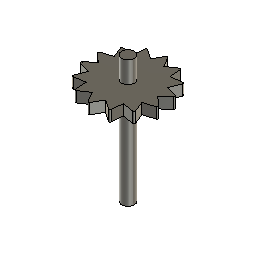
base assembly (Autodesk Fusion 360 archive; units mm, degrees)
design "in gear 2"
part number: 2026-03-27-23-33-12-431
Autodesk Fusion 360 part; units mm, degrees
(part 1 of 2)
sketch "Sketch1" plane through (0, 0, 0) normal (0, 0, 1) x (1, 0, 0)
  circle A0 centre (0, 0) radius 3
  dimension "d1" = 6
  constraint coincident A0.centre origin
  measures "d1" diameter of A0
extrude "Extrude1" add sketch "Sketch1" along normal blind 49.5
sketch "Sketch2" plane through (0, 0, 49.5) normal (0, 0, 1) x (-1, 0, 0)
  circle A0 centre (0, 0) radius 3
  circle A1 centre (0, 0) radius 13.5
  dimension "d4" = 27
  constraint concentric A0 A1
  measures "d4" diameter of A1
extrude "Extrude2" add sketch "Sketch2" against normal blind 5
sketch "Sketch3" plane through (0, 0, 49.5) normal (0, 0, 1) x (-1, 0, 0)
  circle A0 centre (0, 0) radius 13.5
  line L0 (-3.4641, -13.048) -> (0, -19.048)
  line L1 (0, -19.048) -> (3.4641, -13.048)
  line L2 (3.4641, -13.048) -> (-3.4641, -13.048)
  point P0 (0, -15.048)
  dimension "d7" = 2
  constraint horizontal L2
  constraint coincident A0 L1.end
  constraint coincident A0 L0.start
  measures "d7" distance of P0 L2
extrude "Extrude3" add sketch "Sketch3" against normal up to surface (5 mm away) contours A0 L0 L1
fillet "Fillet1" radius 0.5 1 edges at (0, 19.048, 47)
sketch "Sketch5" plane through (0, 0, 49.5) normal (0, 0, 1) x (-1, 0, 0)
  line L0 (-3.4641, -13.048) -> (-0.433, -18.298)
  arc A0 (-0.433, -18.298) -> (0.433, -18.298) centre (0, -18.048) ccw
  line L1 (0.433, -18.298) -> (3.4641, -13.048)
  circle A1 centre (0, 0) radius 3
  arc A2 (3.4641, -13.048) -> (-3.4641, -13.048) centre (0, 0) ccw
  constraint coincident A1.centre A2.centre
extrude "Extrude5" add sketch "Sketch5" along normal blind 10 contours A1
pattern_circular "C-Pattern2" count 14 over 360 about axis through (0, 0, 1.75) along (0, 0, 1) of "Extrude3", "Fillet1"

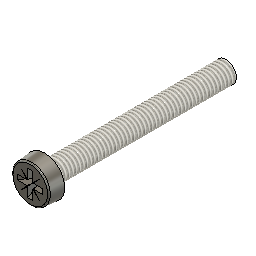
design "Cheese Head Screw NF EN ISO 7048 - M3 x 25 - Z Steel 4.6 Plain"
description: Cheese Head Screw NF EN ISO 7048 - M3 x 25 - Z
part number: NF EN ISO 7048 - Z - M3 x 25 Steel 4.6 Plain
Autodesk Fusion 360 part; units mm, degrees
sketch "Sketch1" plane through (0, 0, 0) normal (0, 1, 0) x (1, 0, 0)
  line L0 (0, -2) -> (0, 25)
  line L1 (-2.75, 0) -> (-2.575, -2)
  line L2 (-2.75, 0) -> (-1.325, 0)
  line L3 (0, 25) -> (-1.5, 25)
  line L4 (-1.5, 25) -> (-1.5, 1)
  line L5 (-1.5, 1) -> (-1.325, 0.3469)
  line L6 (-1.325, 0.3469) -> (-1.325, 0)
  line L7 (0, -2) -> (-2.575, -2)
  dimension "d13" = 5
  dimension "d14" = 5.5
  dimension "d18" = 3
  dimension "d56" = 25
  dimension "d65" = 15
  dimension "d71" = 2.65
  dimension "d77" = 1
  dimension "d97" = 2
  constraint vertical L0
  constraint coincident origin L0
  constraint coincident origin L2
  constraint coincident L2.end L6.end
  constraint perpendicular L0 L7
  measures "d13" angle of L0 L1
  measures "d56" distance of L2 L3
  measures "d65" angle of L5 L6
  measures "d77" distance of L2 L4.end
  measures "d97" distance of L2 L7
revolve "Revolve1" add sketch "Sketch1" angle 360 about axis through (0, 0, 2) along (0, 0, -1) makes body 1
fillet "Fillet3" radius 0.2 1 edges at (-2.4008, 0.9312, 2) on bodies 1
fillet "Fillet2" radius 0.1 1 edges at (-1.2353, 0.4791, 0) on bodies 1
sketch "Sketch2" plane through (0, 0, 2) normal (0, 0, 1) x (1, 0, 0)
  line L0 (-0.42, -0.42) -> (0.42, -0.42)
  line L1 (0.42, -0.42) -> (0.42, 0.42)
  line L2 (0.42, 0.42) -> (-0.42, 0.42)
  line L3 (-0.42, 0.42) -> (-0.42, -0.42)
  dimension "d98" = 0.84
  constraint vertical L1
  measures "d98" distance of L0 L2
extrude "Extrude2" add sketch "Sketch2" against normal blind 0.976 draft -10 separate body makes body 2
sketch "Sketch3" plane through (0, 0, 2) normal (0, 0, 1) x (1, 0, 0)
  circle A0 centre (0, 0) radius 2.3918
  line L0 (-0.35, 0.35) -> (-1.75, 0.35)
  line L1 (-1.75, 0.35) -> (-1.75, -0.35)
  line L2 (-1.75, -0.35) -> (-0.35, -0.35)
  line L3 (-0.35, -0.35) -> (-0.35, -1.75)
  line L4 (-0.35, -1.75) -> (0.35, -1.75)
  line L5 (0.35, -1.75) -> (0.35, -0.35)
  line L6 (0.35, -0.35) -> (1.75, -0.35)
  line L7 (1.75, -0.35) -> (1.75, 0.35)
  line L8 (1.75, 0.35) -> (0.35, 0.35)
  line L9 (0.35, 0.35) -> (0.35, 1.75)
  line L10 (0.35, 1.75) -> (-0.35, 1.75)
  line L11 (-0.35, 1.75) -> (-0.35, 0.35)
  dimension "d86" = 360
  dimension "d87" = 3.5
  dimension "d99" = 0.7
  constraint horizontal L0
  constraint vertical L0.start L2.end
  constraint coincident L0.start L11.end
  constraint perpendicular L7 L8
  measures "d87" distance of L4.end L10
  measures "d99" distance of L0 L2
extrude "Extrude3" add sketch "Sketch3" against normal blind 1.22 draft -4 separate body contours L0 L1 L2 L3 L4 L5 L6 L7 L8 L9 L10 L11 makes body 3
draft "Draft2" angle -30 neutral plane through (0, 0, 2) pull (0, 0, 1) 4 faces at (-0.0882, -1.7216, 1.5933) (-1.7216, 0.0882, 1.5933) (1.7216, 0.0882, 1.5933) (-0.0882, 1.7216, 1.5933) on bodies 3
combine "Combine2" operation cut target body 1 tool bodies 3 2
sketch "Sketch4" plane through (0, 0, 2) normal (0, 0, 1) x (1, 0, 0)
  line L0 (0.42, 0.35) -> (1.75, 0.35)
  line L1 (0.35, 1.75) -> (0.35, 0.42)
  line L2 (0, 0) -> (1.2619, 1.2619) construction
  circle A0 centre (0, 0) radius 1.7847 construction
  line L3 (0.35, 0.42) -> (0.42, 0.35)
  line L4 (0.42, 0.35) -> (1.2619, 1.2619)
  line L5 (0.35, 0.42) -> (1.2619, 1.2619)
  line L6 (-0.42, -0.42) -> (-0.42, -0.35)
  line L7 (-0.42, 0.35) -> (-0.42, 0.42)
  line L8 (-0.42, 0.42) -> (-0.35, 0.42)
  line L9 (0.35, 0.42) -> (0.42, 0.42)
  line L10 (0.42, 0.42) -> (0.42, 0.35)
  line L11 (0.42, -0.35) -> (0.42, -0.42)
  line L12 (0.42, -0.42) -> (0.35, -0.42)
  line L13 (-0.35, -0.42) -> (-0.42, -0.42)
  point P0 (0.42, 0.42)
  constraint coincident L2.start A0.centre
  constraint coincident L1.start A0
  constraint coincident L2.end A0
  constraint coincident L1.end L3.start
  constraint coincident L0.start L3.end
  constraint coincident L2 P0
extrude "Extrude4" cut sketch "Sketch4" against normal blind 2 draft -30 bodies 1
pattern_circular "C-Pattern1" count 4 over 360 about axis through (0, 0, 1.75) along (0, 0, 1) of "Extrude4"
thread "Thread3" "ISO Metric profile 3.0 M3x0.5 M3x0.5 6g" major diameter 2.927 minor diameter 2.3555 pitch 0.5 angle 60 resizes the face on face at (-1.4981, -0.0748, -17) on bodies 1
equation "adsk_nomdia = 3.00 mm"
equation "adsk_nomlen = 25.00 mm"
equation "adsk_headdia = 5.50 mm"
equation "adsk_phildia = 3.50 mm"
equation "adsk_midfillet = 0.10 mm"
equation "adsk_phildepth = 1.22 mm"
equation "adsk_shnklen = 1.00 mm"
equation "adsk_thrang = 15 deg"
equation "adsk_headang = 5 deg"
equation "d13 = adsk_headang"
equation "d14 = adsk_headdia"
equation "d18 = adsk_nomdia"
equation "adsk_philwidth = 0.70 mm"
equation "d52 = adsk_midfillet"
equation "d56 = adsk_nomlen"
equation "d65 = adsk_thrang"
equation "adsk_headh = 2.00 mm"
equation "adsk_pitch1 = 0.50 mm"
equation "adsk_shnkdia = adsk_nomdia - 0.7 * adsk_pitch1"
equation "d71 = adsk_shnkdia"
equation "adsk_headtoprad = adsk_headh * 0.1"
equation "d76 = adsk_headtoprad"
equation "d77 = adsk_shnklen"
equation "d82 = -adsk_phildepth * 0.8"
equation "d87 = adsk_phildia"
equation "d88 = -adsk_phildepth"
equation "d93 = -adsk_headh"
equation "d97 = adsk_headh"
equation "d98 = adsk_philwidth * 1.2"
equation "d99 = adsk_philwidth"

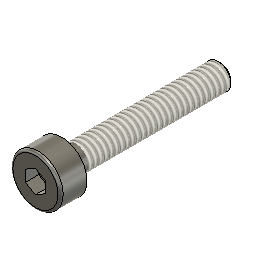
design "Broached Hexagon Socket Head Cap Screw ASME B18.3.1M - M2x0.4 x 12 Steel Grade 2 Plain"
description: Broached Hexagon Socket Head Cap Screw ASME B18.3.1M - M2x0.4 x 12
part number: BSHCS ASME B18.3.1M - M2x0.4 x 12 Steel Grade 2 Plain
Autodesk Fusion 360 part; units mm, degrees
sketch "Sketch1" plane through (0, 0, 0) normal (0, 1, 0) x (1, 0, 0)
  line L0 (-1, 0) -> (-1, 12)
  line L1 (-1, 12) -> (0, 12)
  line L2 (0, 12) -> (0, -2)
  line L3 (-1, 0) -> (-1.9, 0)
  line L4 (-1.9, 0) -> (-1.9, -2)
  line L5 (-1.9, -2) -> (0, -2)
  dimension "d101" = 12
  dimension "d102" = 2
  dimension "d109" = 3.8
  dimension "d110" = 2
  constraint perpendicular L0 L1
  constraint collinear origin L1.end L2.end
  constraint perpendicular L0 L3
  constraint coincident origin L3
  constraint vertical L2
  constraint coincident L2 L5.end
  constraint perpendicular L2 L5
  measures "d101" distance of origin L1
  measures "d102" distance of L3.end L5
revolve "Revolve1" add sketch "Sketch1" angle 360 about axis through (0, 0, -12) along (0, 0, 1)
ref_plane "WorkPlane1" through (0, 0, 2) normal (0, 0, 1) x (1, 0, 0)
sketch "Sketch6" plane through (0, 0, 2) normal (0, 0, 1) x (1, 0, 0)
  line L0 (0, -0.866) -> (0.75, -0.433)
  line L1 (0.75, -0.433) -> (0.75, 0.433)
  line L2 (0.75, 0.433) -> (0, 0.866)
  line L3 (0, 0.866) -> (-0.75, 0.433)
  line L4 (-0.75, 0.433) -> (-0.75, -0.433)
  line L5 (-0.75, -0.433) -> (0, -0.866)
  dimension "d111" = 1.5
  constraint vertical L1
  measures "d111" distance of L1 L4
extrude "Extrude1" cut sketch "Sketch6" against normal blind 1
extrude "Extrude2" cut 1 faces at (0, -0.2887, 1) along direction (0, 0, -1) blind 1 draft -85
thread "Thread3" "ANSI Metric M Profile 2.0 M2x0.4 M2x0.4 4g6g" major diameter 1.9335 minor diameter 1.4905 pitch 0.4 angle 60 resizes the face on face at (-0.995, 0.0996, -8) from (0, 0, -1.0454) to (0, 0, -12)
fillet "Fillet4" radius 0.2 1 edges at (-1.7714, 0.6871, 2)
sketch "Sketch7" plane through (0, 0, 0) normal (0, 1, 0) x (1, 0, 0)
  line L0 (-1.02, 12) -> (-1.02, 11.7546)
  line L1 (-1.02, 11.7546) -> (-0.7546, 12)
  line L2 (0, 12) -> (0, -2)
  line L3 (-1.02, 12) -> (0, 12)
  dimension "d104" = 0.7546
  dimension "d105" = 1.02
  dimension "d106" = 0.2454
  constraint coincident L2.start L3.end
  constraint perpendicular L2 L3
  constraint coincident L1.end L3
  constraint perpendicular L0 L3
  measures "d104" distance of L1.end L2
  measures "d105" distance of L0 L2.start
  measures "d106" distance of L0.end L3
revolve "Revolve3" cut sketch "Sketch7" angle 360 about axis through (0, 0, 1.75) along (0, 0, 1)
equation "adsk_nomlen = 12.00 mm"
equation "adsk_headh = 2.00 mm"
equation "adsk_headdia = 3.80 mm"
equation "adsk_nomdia = 2.00 mm"
equation "adsk_philwidth = 1.50 mm"
equation "d31 = -adsk_phildepth"
equation "adsk_phildepth = 1.00 mm"
equation "d71 = adsk_headh"
equation "d76 = -adsk_phildepth"
equation "adsk_thrlen = 10.95462 mm"
equation "d86 = adsk_nomdia * 0.1"
equation "adsk_startlen = 0.24538 mm"
equation "adsk_endpointdia = 1.50924 mm"
equation "d101 = adsk_nomlen"
equation "d102 = adsk_headh"
equation "d104 = adsk_endpointdia / 2"
equation "d105 = adsk_nomdia * 0.51"
equation "d106 = adsk_startlen"
equation "d108 = min(adsk_thrlen; adsk_nomlen - 0.001 mm)"
equation "d109 = adsk_headdia"
equation "d110 = adsk_nomdia"
equation "d111 = adsk_philwidth"

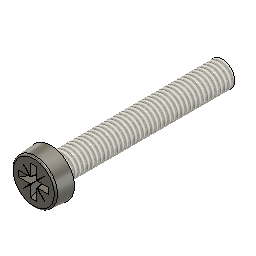
design "Cheese Head Screw NF EN ISO 7048 - M3 x 20 - Z Steel 4.6 Plain"
description: Cheese Head Screw NF EN ISO 7048 - M3 x 20 - Z
part number: NF EN ISO 7048 - Z - M3 x 20 Steel 4.6 Plain
Autodesk Fusion 360 part; units mm, degrees
sketch "Sketch1" plane through (0, 0, 0) normal (0, 1, 0) x (1, 0, 0)
  line L0 (0, -2) -> (0, 20)
  line L1 (-2.75, 0) -> (-2.575, -2)
  line L2 (-2.75, 0) -> (-1.325, 0)
  line L3 (0, 20) -> (-1.5, 20)
  line L4 (-1.5, 20) -> (-1.5, 1)
  line L5 (-1.5, 1) -> (-1.325, 0.3469)
  line L6 (-1.325, 0.3469) -> (-1.325, 0)
  line L7 (0, -2) -> (-2.575, -2)
  dimension "d13" = 5
  dimension "d14" = 5.5
  dimension "d18" = 3
  dimension "d56" = 20
  dimension "d65" = 15
  dimension "d71" = 2.65
  dimension "d77" = 1
  dimension "d97" = 2
  constraint vertical L0
  constraint coincident origin L0
  constraint coincident origin L2
  constraint coincident L2.end L6.end
  constraint perpendicular L0 L7
  measures "d13" angle of L0 L1
  measures "d56" distance of L2 L3
  measures "d65" angle of L5 L6
  measures "d77" distance of L2 L4.end
  measures "d97" distance of L2 L7
revolve "Revolve1" add sketch "Sketch1" angle 360 about axis through (0, 0, 2) along (0, 0, -1) makes body 1
fillet "Fillet3" radius 0.2 1 edges at (-2.4008, 0.9312, 2) on bodies 1
fillet "Fillet2" radius 0.1 1 edges at (-1.2353, 0.4791, 0) on bodies 1
sketch "Sketch2" plane through (0, 0, 2) normal (0, 0, 1) x (1, 0, 0)
  line L0 (-0.42, -0.42) -> (0.42, -0.42)
  line L1 (0.42, -0.42) -> (0.42, 0.42)
  line L2 (0.42, 0.42) -> (-0.42, 0.42)
  line L3 (-0.42, 0.42) -> (-0.42, -0.42)
  dimension "d98" = 0.84
  constraint vertical L1
  measures "d98" distance of L0 L2
extrude "Extrude2" add sketch "Sketch2" against normal blind 0.976 draft -10 separate body makes body 2
sketch "Sketch3" plane through (0, 0, 2) normal (0, 0, 1) x (1, 0, 0)
  circle A0 centre (0, 0) radius 2.3918
  line L0 (-0.35, 0.35) -> (-1.75, 0.35)
  line L1 (-1.75, 0.35) -> (-1.75, -0.35)
  line L2 (-1.75, -0.35) -> (-0.35, -0.35)
  line L3 (-0.35, -0.35) -> (-0.35, -1.75)
  line L4 (-0.35, -1.75) -> (0.35, -1.75)
  line L5 (0.35, -1.75) -> (0.35, -0.35)
  line L6 (0.35, -0.35) -> (1.75, -0.35)
  line L7 (1.75, -0.35) -> (1.75, 0.35)
  line L8 (1.75, 0.35) -> (0.35, 0.35)
  line L9 (0.35, 0.35) -> (0.35, 1.75)
  line L10 (0.35, 1.75) -> (-0.35, 1.75)
  line L11 (-0.35, 1.75) -> (-0.35, 0.35)
  dimension "d86" = 360
  dimension "d87" = 3.5
  dimension "d99" = 0.7
  constraint horizontal L0
  constraint vertical L0.start L2.end
  constraint coincident L0.start L11.end
  constraint perpendicular L7 L8
  measures "d87" distance of L4.end L10
  measures "d99" distance of L0 L2
extrude "Extrude3" add sketch "Sketch3" against normal blind 1.22 draft -4 separate body contours L0 L1 L2 L3 L4 L5 L6 L7 L8 L9 L10 L11 makes body 3
draft "Draft2" angle -30 neutral plane through (0, 0, 2) pull (0, 0, 1) 4 faces at (-0.0882, -1.7216, 1.5933) (-1.7216, 0.0882, 1.5933) (1.7216, 0.0882, 1.5933) (-0.0882, 1.7216, 1.5933) on bodies 3
combine "Combine2" operation cut target body 1 tool bodies 3 2
sketch "Sketch4" plane through (0, 0, 2) normal (0, 0, 1) x (1, 0, 0)
  line L0 (0.42, 0.35) -> (1.75, 0.35)
  line L1 (0.35, 1.75) -> (0.35, 0.42)
  line L2 (0, 0) -> (1.2619, 1.2619) construction
  circle A0 centre (0, 0) radius 1.7847 construction
  line L3 (0.35, 0.42) -> (0.42, 0.35)
  line L4 (0.42, 0.35) -> (1.2619, 1.2619)
  line L5 (0.35, 0.42) -> (1.2619, 1.2619)
  line L6 (-0.42, -0.42) -> (-0.42, -0.35)
  line L7 (-0.42, 0.35) -> (-0.42, 0.42)
  line L8 (-0.42, 0.42) -> (-0.35, 0.42)
  line L9 (0.35, 0.42) -> (0.42, 0.42)
  line L10 (0.42, 0.42) -> (0.42, 0.35)
  line L11 (0.42, -0.35) -> (0.42, -0.42)
  line L12 (0.42, -0.42) -> (0.35, -0.42)
  line L13 (-0.35, -0.42) -> (-0.42, -0.42)
  point P0 (0.42, 0.42)
  constraint coincident L2.start A0.centre
  constraint coincident L1.start A0
  constraint coincident L2.end A0
  constraint coincident L1.end L3.start
  constraint coincident L0.start L3.end
  constraint coincident L2 P0
extrude "Extrude4" cut sketch "Sketch4" against normal blind 2 draft -30 bodies 1
pattern_circular "C-Pattern1" count 4 over 360 about axis through (0, 0, 1.75) along (0, 0, 1) of "Extrude4"
thread "Thread3" "ISO Metric profile 3.0 M3x0.5 M3x0.5 6g" major diameter 2.927 minor diameter 2.3555 pitch 0.5 angle 60 resizes the face on face at (-1.4925, -0.1494, -13.6667) on bodies 1
equation "adsk_nomdia = 3.00 mm"
equation "adsk_nomlen = 20.00 mm"
equation "adsk_headdia = 5.50 mm"
equation "adsk_phildia = 3.50 mm"
equation "adsk_midfillet = 0.10 mm"
equation "adsk_phildepth = 1.22 mm"
equation "adsk_shnklen = 1.00 mm"
equation "adsk_thrang = 15 deg"
equation "adsk_headang = 5 deg"
equation "d13 = adsk_headang"
equation "d14 = adsk_headdia"
equation "d18 = adsk_nomdia"
equation "adsk_philwidth = 0.70 mm"
equation "d52 = adsk_midfillet"
equation "d56 = adsk_nomlen"
equation "d65 = adsk_thrang"
equation "adsk_headh = 2.00 mm"
equation "adsk_pitch1 = 0.50 mm"
equation "adsk_shnkdia = adsk_nomdia - 0.7 * adsk_pitch1"
equation "d71 = adsk_shnkdia"
equation "adsk_headtoprad = adsk_headh * 0.1"
equation "d76 = adsk_headtoprad"
equation "d77 = adsk_shnklen"
equation "d82 = -adsk_phildepth * 0.8"
equation "d87 = adsk_phildia"
equation "d88 = -adsk_phildepth"
equation "d93 = -adsk_headh"
equation "d97 = adsk_headh"
equation "d98 = adsk_philwidth * 1.2"
equation "d99 = adsk_philwidth"

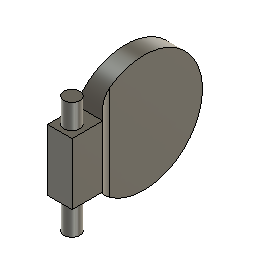
design "closing element"
part number: 2026-03-27-16-31-58-847
Autodesk Fusion 360 part; units mm, degrees
sketch "Sketch1" plane through (0, 0, 0) normal (1, 0, 0) x (0, 1, 0)
  circle A0 centre (0, 0) radius 9.5
  dimension "d1" = 19
  constraint coincident A0.centre origin
  measures "d1" diameter of A0
extrude "Extrude1" add sketch "Sketch1" along normal blind 3
sketch "Sketch2" plane through (3, 0, 0) normal (1, 0, 0) x (0, 1, 0)
  circle A0 centre (0, 0) radius 9.5
  line L0 (-8.0777, 5) -> (-13.0777, 5)
  line L1 (-13.0777, 5) -> (-13.0777, -5)
  line L2 (-13.0777, -5) -> (-8.0777, -5)
  line L3 (-8.0777, -5) -> (-8.0777, 5)
  dimension "d4" = 5
  dimension "d5" = 10
  constraint horizontal L0
  constraint vertical L1
  constraint horizontal L2
  constraint vertical L3
  constraint coincident A0 L0.start
  constraint coincident A0 L2.end
  measures "d4" distance of L0.start L0.end
  measures "d5" distance of L0.start L2.end
extrude "Extrude2" add sketch "Sketch2" along normal blind 1 contours A0 L3 | A0 L0 L1 L2 picked at (-8.2821, 1.2788)
extrude "Extrude3" add 1 faces at (3, -11.8852, 0) along direction (-1, 0, 0) blind 2.6
extrude "Extrude4" add 1 faces at (4, -11.4111, 1.6667) along direction (1, 0, 0) blind 0.4
sketch "Sketch3" plane through (0, 0, -5) normal (0, 0, -1) x (1, 0, 0)
  line L0 (3, 8.0777) -> (4.4, 8.0777)
  line L1 (4.4, 8.0777) -> (4.4, 13.0777)
  line L2 (4.4, 13.0777) -> (0.4, 13.0777)
  line L3 (0.4, 13.0777) -> (0.4, 8.0777)
  line L4 (0.4, 8.0777) -> (3, 8.0777)
  line L5 (4.4, 13.0777) -> (0.4, 13.0777)
  line L6 (0.4, 13.0777) -> (0.4, 8.0777)
  line L7 (0.4, 8.0777) -> (4.4, 8.0777)
  line L8 (4.4, 8.0777) -> (4.4, 13.0777)
  circle A0 centre (2.36, 11.0777) radius 1.3
  dimension "d12" = 2.6
  dimension "d21" = 2
  constraint horizontal L5
  constraint vertical L6
  constraint horizontal L7
  constraint vertical L8
  constraint coincident L3.end L4.start
  constraint coincident L1.end L2.start
  measures "d12" diameter of A0
  measures "d21" distance of L5 A0.centre
extrude "Extrude5" add sketch "Sketch3" along normal blind 5 and the other way blind 14 contours A0
fillet "Fillet1" radius 3 1 edges at (3, -8.0777, 0)
fillet "Fillet1" radius 1 1 edges at (0.4, -9.5, 0)

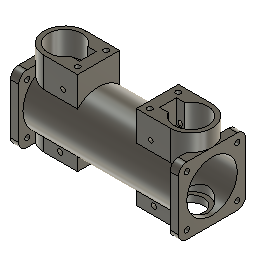
design "hub"
part number: 2026-03-27-13-33-24-088
Autodesk Fusion 360 part; units mm, degrees
sketch "Sketch1" plane through (0, 0, 0) normal (1, 0, 0) x (0, 1, 0)
  circle A0 centre (0, 0) radius 15
  circle A1 centre (0, 0) radius 17.5
  constraint coincident A0.centre A1.centre
  constraint concentric A0 A1
extrude "Extrude1" add sketch "Sketch1" along normal blind 50
extrude "Extrude2" add 1 faces at (0, 6.9889, -15.0815) along direction (-1, 0, 0) blind 50
sketch "Sketch3" plane through (-50, 0, 0) normal (-1, 0, 0) x (0, -1, 0)
  circle A0 centre (0, 0) radius 15
  circle A1 centre (0, 0) radius 17.5
  circle A2 centre (0, 0) radius 15
  line L0 (-15, 20) -> (15, 20)
  line L1 (20, 15) -> (20, -15)
  line L2 (15, -20) -> (-15, -20)
  line L3 (-20, -15) -> (-20, 15)
  line L4 (-20, 20) -> (20, -20) construction
  line L5 (20, 20) -> (-20, -20) construction
  arc A3 (-15, 20) -> (-20, 15) centre (-15, 15) ccw
  arc A4 (20, 15) -> (15, 20) centre (15, 15) ccw
  arc A5 (15, -20) -> (20, -15) centre (15, -15) ccw
  arc A6 (-20, -15) -> (-15, -20) centre (-15, -15) ccw
  circle A7 centre (-15, 15) radius 1.5
  circle A8 centre (15, 15) radius 1.5
  circle A9 centre (15, -15) radius 1.5
  circle A10 centre (-15, -15) radius 1.5
  constraint coincident A0.centre A1.centre
  constraint horizontal L0
  constraint perpendicular L0 L1
  constraint parallel L0 L2
  constraint parallel L1 L3
  constraint coincident L4 A0.centre
  constraint coincident L5 A0.centre
  constraint coincident L4.start L0
  constraint coincident L4.start L3
  constraint tangent L0 A3
  constraint tangent L3 A3
  constraint coincident L5.start L0
  constraint coincident L5.start L1
  constraint tangent L0 A4
  constraint tangent L1 A4
  constraint coincident L4.end L1
  constraint coincident L4.end L2
  constraint tangent L1 A5
  constraint tangent L2 A5
  constraint equal A4 A5
  constraint coincident L5.end L2
  constraint coincident L5.end L3
  constraint tangent L2 A6
  constraint tangent L3 A6
  constraint equal A4 A6
  constraint concentric A3 A7
  constraint concentric A4 A8
  constraint concentric A5 A9
  constraint concentric A6 A10
  constraint equal A7 A8
  constraint equal A8 A10
  constraint equal A9 A10
extrude "Extrude3" add sketch "Sketch3" against normal blind 5 contours L0 L1 L2 L3 A3 A4 A5 A6
mirror "Mirror1" about plane through (0, 0, 0) normal (1, 0, 0) of "Extrude3"
sketch "Sketch4" plane through (0, 0, 0) normal (0, 0, 1) x (1, 0, 0)
  circle A0 centre (-37.5, 0) radius 12.5
  line L0 (-50, 15) -> (-50, -15)
  circle A1 centre (-37.5, 0) radius 10
  constraint tangent A0 L0
  constraint concentric A0 A1
extrude "Extrude4" add sketch "Sketch4" along normal up to surface (20 mm away) contours A0 | A1
sketch "Sketch5" plane through (0, 0, 20) normal (0, 0, 1) x (-1, 0, 0)
  line L0 (45, -10) -> (45, -15)
  line L1 (45, -15) -> (50, -15)
  line L2 (50, -15) -> (50, 15)
  line L3 (50, 15) -> (45, 15)
  line L4 (45, 15) -> (45, 10)
  arc A0 (45, 10) -> (45, -10) centre (37.5, 0) ccw
  circle A1 centre (37.5, 0) radius 10
  constraint concentric A0 A1
extrude "Extrude5" cut sketch "Sketch5" against normal blind 5 contours A1
sketch "Sketch6" plane through (0, 0, 20) normal (0, 0, 1) x (-1, 0, 0)
  circle A0 centre (37.5, 0) radius 10
  line L0 (45, -10) -> (45, -15)
  line L1 (45, -15) -> (50, -15)
  line L2 (50, -15) -> (50, 15)
  line L3 (50, 15) -> (45, 15)
  line L4 (45, 15) -> (45, 10)
  arc A1 (45, 10) -> (45, -10) centre (37.5, 0) ccw
  arc A2 (45, 10) -> (45, -10) centre (37.5, 0) ccw
  line L5 (37.5, -12.5) -> (17.5, -12.5)
  line L6 (37.5, 12.5) -> (17.5, 12.5)
  line L7 (17.5, -12.5) -> (17.5, 12.5)
  constraint coincident A2 L5.start
  constraint horizontal L5
  constraint tangent A1 L5
  constraint coincident A1 L6.start
  constraint parallel L5 L6
  constraint tangent A2 L6
  constraint perpendicular L6 L7
extrude "Extrude6" add sketch "Sketch6" along normal up to surface contours A1 A2 L5 L6 L7 end surface at (15, -15.1577, 8.7461)
sketch "Sketch7" plane through (0, 0, 20) normal (0, 0, 1) x (-1, 0, 0)
  circle A0 centre (37.5, 0) radius 10
  line L0 (45, -10) -> (45, -15)
  line L1 (45, -15) -> (50, -15)
  line L2 (50, -15) -> (50, 15)
  line L3 (50, 15) -> (45, 15)
  line L4 (45, 15) -> (45, 10)
  arc A1 (45, 10) -> (37.5, 12.5) centre (37.5, 0) ccw
  line L5 (37.5, 12.5) -> (17.5, 12.5)
  line L6 (17.5, 12.5) -> (17.5, -12.5)
  line L7 (17.5, -12.5) -> (37.5, -12.5)
  arc A2 (37.5, -12.5) -> (45, -10) centre (37.5, 0) ccw
  line L8 (28.8397, -5) -> (23.8397, -5)
  line L9 (23.8397, -5) -> (23.8397, 5)
  line L10 (23.8397, 5) -> (28.8397, 5)
  line L11 (28.8397, 5) -> (28.8397, -5)
  constraint horizontal L8
  constraint vertical L9
  constraint horizontal L10
  constraint vertical L11
  constraint coincident A0 L8.start
extrude "Extrude7" cut sketch "Sketch7" against normal up to surface (5 mm away) contours A0 L8 L9 L10
sketch "Sketch8" plane through (-50, 0, 0) normal (-1, 0, 0) x (0, -1, 0)
  line L0 (15, 20) -> (-15, 20)
  arc A0 (-15, 20) -> (-20, 15) centre (-15, 15) ccw
  line L1 (-20, 15) -> (-20, -15)
  arc A1 (-20, -15) -> (-15, -20) centre (-15, -15) ccw
  line L2 (-15, -20) -> (15, -20)
  arc A2 (15, -20) -> (20, -15) centre (15, -15) ccw
  line L3 (20, -15) -> (20, 15)
  arc A3 (20, 15) -> (15, 20) centre (15, 15) ccw
  circle A4 centre (0, 0) radius 15
  circle A5 centre (-15, 15) radius 1.5
  circle A6 centre (-15, -15) radius 1.5
  circle A7 centre (15, 15) radius 1.5
  circle A8 centre (15, -15) radius 1.5
extrude "Extrude8" cut sketch "Sketch8" against normal blind 101 contours A4
sketch "Sketch9" plane through (0, 0, 20) normal (0, 0, 1) x (-1, 0, 0)
  line L0 (45, -10) -> (45, -15)
  line L1 (45, -15) -> (50, -15)
  line L2 (50, -15) -> (50, 15)
  line L3 (50, 15) -> (45, 15)
  line L4 (45, 15) -> (45, 10)
  arc A0 (45, 10) -> (37.5, 12.5) centre (37.5, 0) ccw
  line L5 (37.5, 12.5) -> (17.5, 12.5)
  line L6 (17.5, 12.5) -> (17.5, -12.5)
  line L7 (17.5, -12.5) -> (37.5, -12.5)
  arc A1 (37.5, -12.5) -> (45, -10) centre (37.5, 0) ccw
  line L8 (28.8397, -5) -> (23.8397, -5)
  line L9 (23.8397, -5) -> (23.8397, 5)
  line L10 (23.8397, 5) -> (28.8397, 5)
  arc A2 (28.8397, -5) -> (28.8397, 5) centre (37.5, 0) ccw
  circle A3 centre (37.5, 0) radius 7.433
  constraint concentric A0 A3
extrude "Extrude9" cut sketch "Sketch9" against normal blind 8 contours A3
extrude "Extrude10" add 1 faces at (-25.8932, 3.3333, 15) along direction (0, 0, 1) blind 1
extrude "Extrude11" add 1 faces at (-25.5064, -3.3333, 15) along direction (0, 0, 1) blind 1
sketch "Sketch10" plane through (0, 5, 0) normal (0, -1, 0) x (1, 0, 0)
  line L0 (-28.8397, 16) -> (-23.8397, 16)
  line L1 (-23.8397, 16) -> (-23.8397, 20)
  line L2 (-23.8397, 20) -> (-28.8397, 20)
  line L3 (-28.8397, 20) -> (-28.8397, 16)
  line L4 (-28.8397, 20) -> (-23.3767, 20)
  line L5 (-23.3767, 20) -> (-23.3767, 16)
  line L6 (-23.3767, 16) -> (-28.8397, 16)
  line L7 (-28.8397, 16) -> (-28.8397, 20)
  line L8 (-28.8397, 20) -> (-23.3767, 16) construction
  line L9 (-23.3767, 20) -> (-28.8397, 16) construction
  circle A0 centre (-26.1082, 18) radius 1.3481
  point P0 (-26.1082, 18)
  constraint horizontal L4
  constraint perpendicular L4 L5
  constraint parallel L4 L6
  constraint parallel L5 L7
  constraint coincident L8 P0
  constraint coincident L9 P0
  constraint coincident L2.end L3.start
  constraint coincident L0 L3.end
  constraint coincident P0 A0.centre
extrude "Extrude12" cut sketch "Sketch10" along normal blind 18 and the other way blind 8 contours A0
mirror "Mirror2" about plane through (0, 0, 0) normal (1, 0, 0) of "Extrude4", "Extrude5", "Extrude6", "Extrude7", "Extrude8", "Extrude9", "Extrude10", "Extrude11", "Extrude12"
sketch "Sketch11" plane through (0, 0, 0) normal (0, 0, 1) x (1, 0, 0)
  line L0 (-50, -15) -> (-50, 15)
  line L1 (-37.5, -12.5) -> (-17.5, -12.5)
  line L2 (-17.5, -12.5) -> (-17.5, 12.5)
  line L3 (-17.5, 12.5) -> (-37.5, 12.5)
  arc A0 (-37.5, 12.5) -> (-37.5, -12.5) centre (-37.5, 0) ccw
  line L4 (-28.8397, -5) -> (-23.8397, -5)
  line L5 (-23.8397, -5) -> (-23.8397, 5)
  line L6 (-23.8397, 5) -> (-28.8397, 5)
  arc A1 (-28.8397, 5) -> (-28.8397, -5) centre (-37.5, 0) ccw
  constraint tangent L0 A0
  constraint concentric A0 A1
  constraint horizontal L1
  constraint vertical L2
  constraint horizontal L3
  constraint tangent L1 A0
  constraint tangent L3 A0
  constraint horizontal L4
  constraint vertical L5
  constraint horizontal L6
extrude "Extrude13" add sketch "Sketch11" against normal up to surface (20 mm away)
sketch "Sketch12" plane through (-50, 0, 0) normal (-1, 0, 0) x (0, -1, 0)
  line L0 (-15, -20) -> (15, -20)
  arc A0 (15, -20) -> (20, -15) centre (15, -15) ccw
  line L1 (20, -15) -> (20, 15)
  arc A1 (20, 15) -> (15, 20) centre (15, 15) ccw
  line L2 (15, 20) -> (-15, 20)
  arc A2 (-15, 20) -> (-20, 15) centre (-15, 15) ccw
  line L3 (-20, 15) -> (-20, -15)
  arc A3 (-20, -15) -> (-15, -20) centre (-15, -15) ccw
  circle A4 centre (0, 0) radius 15
  circle A5 centre (-15, 15) radius 1.5
  circle A6 centre (-15, -15) radius 1.5
  circle A7 centre (15, 15) radius 1.5
  circle A8 centre (15, -15) radius 1.5
extrude "Extrude14" cut sketch "Sketch12" against normal blind 103 contours A4
sketch "Sketch13" plane through (0, 0, -20) normal (0, 0, -1) x (1, 0, 0)
  line L0 (-45, 10) -> (-45, 15)
  line L1 (-45, 15) -> (-50, 15)
  line L2 (-50, 15) -> (-50, -15)
  line L3 (-50, -15) -> (-45, -15)
  line L4 (-45, -15) -> (-45, -10)
  arc A0 (-45, -10) -> (-37.5, -12.5) centre (-37.5, 0) ccw
  line L5 (-37.5, -12.5) -> (-17.5, -12.5)
  line L6 (-17.5, -12.5) -> (-17.5, 12.5)
  line L7 (-17.5, 12.5) -> (-37.5, 12.5)
  arc A1 (-37.5, 12.5) -> (-45, 10) centre (-37.5, 0) ccw
  arc A2 (-28.8397, 5) -> (-45, 6.6144) centre (-37.5, 0) ccw
  line L8 (-28.8397, 5) -> (-23.8397, 5)
  line L9 (-23.8397, 5) -> (-23.8397, -5)
  line L10 (-23.8397, -5) -> (-28.8397, -5)
  arc A3 (-45, -6.6144) -> (-28.8397, -5) centre (-37.5, 0) ccw
  line L11 (-45, -6.6144) -> (-45, 6.6144)
  circle A4 centre (-37.5, 0) radius 10
  constraint concentric A0 A4
extrude "Extrude15" cut sketch "Sketch13" against normal blind 7 contours A2 A3 L11 A4 | L11 A4
sketch "Sketch14" plane through (0, 0, -20) normal (0, 0, -1) x (1, 0, 0)
  arc A0 (-28.8397, 5) -> (-28.8397, -5) centre (-37.5, 0) ccw
  line L0 (-28.8397, 5) -> (-23.8397, 5)
  line L1 (-23.8397, 5) -> (-23.8397, -5)
  line L2 (-23.8397, -5) -> (-28.8397, -5)
  line L3 (-45, 10) -> (-45, 15)
  line L4 (-45, 15) -> (-50, 15)
  line L5 (-50, 15) -> (-50, -15)
  line L6 (-50, -15) -> (-45, -15)
  line L7 (-45, -15) -> (-45, -10)
  arc A1 (-45, -10) -> (-37.5, -12.5) centre (-37.5, 0) ccw
  line L8 (-37.5, -12.5) -> (-17.5, -12.5)
  line L9 (-17.5, -12.5) -> (-17.5, 12.5)
  line L10 (-17.5, 12.5) -> (-37.5, 12.5)
  arc A2 (-37.5, 12.5) -> (-45, 10) centre (-37.5, 0) ccw
  line L11 (-28.8397, 5) -> (-26.8397, 5)
  line L12 (-26.8397, 5) -> (-26.8397, -5)
  line L13 (-26.8397, -5) -> (-28.8397, -5)
  line L14 (-28.8397, -5) -> (-28.8397, 5)
  constraint horizontal L11
  constraint vertical L12
  constraint horizontal L13
  constraint vertical L14
  constraint coincident L2 L12.end
  constraint coincident A0.start L0.start
extrude "Extrude16" cut sketch "Sketch14" against normal blind 9 contours L0 L2 L11 L12 L13 L14
sketch "Sketch15" plane through (0, 0, -20) normal (0, 0, -1) x (1, 0, 0)
  arc A0 (-28.8397, 5) -> (-28.8397, -5) centre (-37.5, 0) ccw
  line L0 (-28.8397, 5) -> (-23.8397, 5)
  line L1 (-23.8397, 5) -> (-23.8397, -5)
  line L2 (-23.8397, -5) -> (-28.8397, -5)
  line L3 (-45, 10) -> (-45, 15)
  line L4 (-45, 15) -> (-50, 15)
  line L5 (-50, 15) -> (-50, -15)
  line L6 (-50, -15) -> (-45, -15)
  line L7 (-45, -15) -> (-45, -10)
  arc A1 (-45, -10) -> (-37.5, -12.5) centre (-37.5, 0) ccw
  line L8 (-37.5, -12.5) -> (-17.5, -12.5)
  line L9 (-17.5, -12.5) -> (-17.5, 12.5)
  line L10 (-17.5, 12.5) -> (-37.5, 12.5)
  arc A2 (-37.5, 12.5) -> (-45, 10) centre (-37.5, 0) ccw
  circle A3 centre (-37.5, 0) radius 7.5
  arc A4 (-28.8397, 5) -> (-28.8397, -5) centre (-37.5, 0) ccw
  line L11 (-23.8397, 5) -> (-28.8397, 5)
  line L12 (-23.8397, -5) -> (-23.8397, 5)
  line L13 (-28.8397, -5) -> (-23.8397, -5)
  constraint concentric A0 A3
extrude "Extrude17" add sketch "Sketch15" against normal blind 4 contours A0 L0 L1 L2 A4 L11 L12 L13
extrude "Extrude18" cut 2 faces at (-39.0496, 7.9401, -13) (-38.298, -8.2253, -13) along direction (0, 0, 1) blind 4
sketch "Sketch16" plane through (0, 5, 0) normal (0, -1, 0) x (1, 0, 0)
  line L0 (-28.8397, -16) -> (-26.8397, -16)
  line L1 (-26.8397, -16) -> (-26.8397, -14.1421)
  line L2 (-26.8397, -14.1421) -> (-28.8397, -14.1421)
  line L3 (-28.8397, -14.1421) -> (-28.8397, -16)
  line L4 (-28.8397, -14.1421) -> (-26.8397, -14.1421)
  line L5 (-26.8397, -14.1421) -> (-26.8397, -16)
  line L6 (-26.8397, -16) -> (-28.8397, -16)
  line L7 (-28.8397, -16) -> (-28.8397, -14.1421)
  line L8 (-28.8397, -14.1421) -> (-26.8397, -16) construction
  line L9 (-26.8397, -14.1421) -> (-28.8397, -16) construction
  circle A0 centre (-27.8397, -15.0711) radius 1.5
  point P0 (-27.8397, -15.0711)
  constraint horizontal L4
  constraint perpendicular L4 L5
  constraint parallel L4 L6
  constraint parallel L5 L7
  constraint coincident L8 P0
  constraint coincident L9 P0
  constraint coincident L2.end L3.start
  constraint coincident P0 A0.centre
extrude "Extrude19" cut sketch "Sketch16" along normal blind 20 and the other way blind 25 contours L0 L1 L2 L3 L4 L5 L6 L7 | A0
mirror "Mirror3" about plane through (0, 0, 0) normal (1, 0, 0) of "Extrude13", "Extrude14", "Extrude15", "Extrude16", "Extrude17", "Extrude18", "Extrude19"
sketch "Sketch17" plane through (-50, 0, 0) normal (-1, 0, 0) x (0, -1, 0)
  line L0 (-15, -20) -> (15, -20)
  arc A0 (15, -20) -> (20, -15) centre (15, -15) ccw
  line L1 (20, -15) -> (20, 15)
  arc A1 (20, 15) -> (15, 20) centre (15, 15) ccw
  line L2 (15, 20) -> (-15, 20)
  arc A2 (-15, 20) -> (-20, 15) centre (-15, 15) ccw
  line L3 (-20, 15) -> (-20, -15)
  arc A3 (-20, -15) -> (-15, -20) centre (-15, -15) ccw
  circle A4 centre (0, 0) radius 15
  circle A5 centre (-15, 15) radius 1.5
  circle A6 centre (-15, -15) radius 1.5
  circle A7 centre (15, 15) radius 1.5
  circle A8 centre (15, -15) radius 1.5
  circle A9 centre (0, 0) radius 15
  constraint coincident A4.centre A9.centre
extrude "Extrude20" add sketch "Sketch17" against normal blind 2 contours A4 A9
sketch "Sketch18" plane through (0, 0, 20) normal (0, 0, 1) x (-1, 0, 0)
  line L0 (-45, 10) -> (-45, 15)
  line L1 (-45, 15) -> (-50, 15)
  line L2 (-50, 15) -> (-50, -15)
  line L3 (-50, -15) -> (-45, -15)
  line L4 (-45, -15) -> (-45, -10)
  arc A0 (-45, -10) -> (-37.5, -12.5) centre (-37.5, 0) ccw
  line L5 (-37.5, -12.5) -> (-17.5, -12.5)
  line L6 (-17.5, -12.5) -> (-17.5, 12.5)
  line L7 (-17.5, 12.5) -> (-37.5, 12.5)
  arc A1 (-37.5, 12.5) -> (-45, 10) centre (-37.5, 0) ccw
  line L8 (-28.8397, 5) -> (-23.8397, 5)
  line L9 (-23.8397, 5) -> (-23.8397, -5)
  line L10 (-23.8397, -5) -> (-28.8397, -5)
  arc A2 (-28.8397, 5) -> (-28.8397, -5) centre (-37.5, 0) ccw
  circle A3 centre (-37.5, 0) radius 7.433
  line L11 (-23.8397, -5) -> (-23.8397, 5)
  line L12 (-23.8397, 5) -> (-28.8397, 5)
  arc A4 (-28.8397, 5) -> (-28.8397, -5) centre (-37.5, 0) ccw
  line L13 (-28.8397, -5) -> (-23.8397, -5)
  line L14 (23.8397, 5) -> (23.8397, -5)
  line L15 (23.8397, -5) -> (28.8397, -5)
  arc A5 (28.8397, -5) -> (28.8397, 5) centre (37.5, 0) ccw
  line L16 (28.8397, 5) -> (23.8397, 5)
  circle A6 centre (37.5, 0) radius 7.433
  line L17 (45, -10) -> (45, -15)
  line L18 (45, -15) -> (50, -15)
  line L19 (50, -15) -> (50, 15)
  line L20 (50, 15) -> (45, 15)
  line L21 (45, 15) -> (45, 10)
  arc A7 (45, 10) -> (37.5, 12.5) centre (37.5, 0) ccw
  line L22 (37.5, 12.5) -> (17.5, 12.5)
  line L23 (17.5, 12.5) -> (17.5, -12.5)
  line L24 (17.5, -12.5) -> (37.5, -12.5)
  arc A8 (37.5, -12.5) -> (45, -10) centre (37.5, 0) ccw
  line L25 (28.8397, -5) -> (23.8397, -5)
  line L26 (23.8397, -5) -> (23.8397, 5)
  line L27 (23.8397, 5) -> (28.8397, 5)
  arc A9 (28.8397, -5) -> (28.8397, 5) centre (37.5, 0) ccw
  circle A10 centre (37.5, 0) radius 12.5
  circle A11 centre (-37.5, 0) radius 10
  circle A12 centre (-37.5, 0) radius 12.5
  constraint concentric A5 A10
  constraint coincident L17.start A10
  constraint concentric A3 A11
  constraint concentric A3 A12
  constraint coincident L0.start A12
extrude "Extrude21" add sketch "Sketch18" along normal blind 10 contours A0 A1 L8 L10 A2 L12 A4 L13 A11 A12 | L5 L6 L7 L8 L9 L10 L11 L12 L13 A12 | L14 L15 L16 L22 L23 L24 L25 L26 L27 A10 | L15 A5 L16 A7 A8 L25 L27 A9 A10
sketch "Sketch19" plane through (0, 0, 30) normal (0, 0, 1) x (-1, 0, 0)
  line L0 (28.8397, -5) -> (23.8397, -5)
  line L1 (23.8397, -5) -> (23.8397, 5)
  line L2 (23.8397, 5) -> (28.8397, 5)
  arc A0 (28.8397, -5) -> (28.8397, 5) centre (37.5, 0) ccw
  arc A1 (37.5, -12.5) -> (37.5, 12.5) centre (37.5, 0) ccw
  line L3 (37.5, 12.5) -> (17.5, 12.5)
  line L4 (17.5, 12.5) -> (17.5, -12.5)
  line L5 (17.5, -12.5) -> (37.5, -12.5)
  line L6 (-28.8397, 5) -> (-23.8397, 5)
  line L7 (-23.8397, 5) -> (-23.8397, -5)
  line L8 (-23.8397, -5) -> (-28.8397, -5)
  arc A2 (-28.8397, 5) -> (-28.8397, -5) centre (-37.5, 0) ccw
  line L9 (-17.5, 12.5) -> (-37.5, 12.5)
  arc A3 (-37.5, 12.5) -> (-37.5, -12.5) centre (-37.5, 0) ccw
  line L10 (-37.5, -12.5) -> (-17.5, -12.5)
  line L11 (-17.5, -12.5) -> (-17.5, 12.5)
  arc A4 (37.5, -8.5) -> (37.5, 8.5) centre (37.5, 0) ccw
  line L12 (37.5, 8.5) -> (21.5, 8.5)
  line L13 (21.5, 8.5) -> (21.5, -8.5)
  line L14 (21.5, -8.5) -> (37.5, -8.5)
  line L15 (-21.5, 8.5) -> (-37.5, 8.5)
  arc A5 (-37.5, 8.5) -> (-37.5, -8.5) centre (-37.5, 0) ccw
  line L16 (-37.5, -8.5) -> (-21.5, -8.5)
  line L17 (-21.5, -8.5) -> (-21.5, 8.5)
  circle A6 centre (21.5, -8.5) radius 1.5
  circle A7 centre (21.5, 8.5) radius 1.5
  circle A8 centre (-21.5, -8.5) radius 1.5
  circle A9 centre (-21.5, 8.5) radius 1.5
  constraint coincident L13.end L14.start
  constraint coincident L12.end L13.start
  constraint coincident L16.end L17.start
  constraint coincident L15.start L17.end
  constraint equal A6 A8
  constraint equal A8 A9
  constraint equal A7 A9
extrude "Extrude22" cut sketch "Sketch19" against normal blind 5 contours L13 L14 A6 | L13 L14 A6 | L12 L13 A7 | L12 L13 A7 | L15 L17 A9 | L15 L17 A9 | L16 L17 A8 | L16 L17 A8
sketch "Sketch20" plane through (0, 0, -20) normal (0, 0, -1) x (1, 0, 0)
  circle A0 centre (37.5, 0) radius 7.5
  line L0 (45, -10) -> (45, -15)
  line L1 (45, -15) -> (50, -15)
  line L2 (50, -15) -> (50, 15)
  line L3 (50, 15) -> (45, 15)
  line L4 (45, 15) -> (45, 10)
  arc A1 (45, 10) -> (37.5, 12.5) centre (37.5, 0) ccw
  line L5 (37.5, 12.5) -> (17.5, 12.5)
  line L6 (17.5, 12.5) -> (17.5, -12.5)
  line L7 (17.5, -12.5) -> (37.5, -12.5)
  arc A2 (37.5, -12.5) -> (45, -10) centre (37.5, 0) ccw
  circle A3 centre (-37.5, 0) radius 7.5
  line L8 (-45, 10) -> (-45, 15)
  line L9 (-45, 15) -> (-50, 15)
  line L10 (-50, 15) -> (-50, -15)
  line L11 (-50, -15) -> (-45, -15)
  line L12 (-45, -15) -> (-45, -10)
  arc A4 (-45, -10) -> (-37.5, -12.5) centre (-37.5, 0) ccw
  line L13 (-37.5, -12.5) -> (-17.5, -12.5)
  line L14 (-17.5, -12.5) -> (-17.5, 12.5)
  line L15 (-17.5, 12.5) -> (-37.5, 12.5)
  arc A5 (-37.5, 12.5) -> (-45, 10) centre (-37.5, 0) ccw
  arc A6 (37.5, -8.5) -> (42.6, -6.8) centre (37.5, 0) ccw
  arc A7 (46, -6.127) -> (42.6, -6.8) centre (45, -10) ccw
  line L16 (46, -6.127) -> (46, 6.127)
  arc A8 (42.6, 6.8) -> (46, 6.127) centre (45, 10) ccw
  arc A9 (42.6, 6.8) -> (37.5, 8.5) centre (37.5, 0) ccw
  line L17 (37.5, 8.5) -> (21.5, 8.5)
  line L18 (21.5, 8.5) -> (21.5, -8.5)
  line L19 (21.5, -8.5) -> (37.5, -8.5)
  arc A10 (-37.5, 8.5) -> (-42.6, 6.8) centre (-37.5, 0) ccw
  arc A11 (-46, 6.127) -> (-42.6, 6.8) centre (-45, 10) ccw
  line L20 (-46, 6.127) -> (-46, -6.127)
  arc A12 (-42.6, -6.8) -> (-46, -6.127) centre (-45, -10) ccw
  arc A13 (-42.6, -6.8) -> (-37.5, -8.5) centre (-37.5, 0) ccw
  line L21 (-37.5, -8.5) -> (-21.5, -8.5)
  line L22 (-21.5, -8.5) -> (-21.5, 8.5)
  line L23 (-21.5, 8.5) -> (-37.5, 8.5)
  circle A14 centre (21.5, -8.5) radius 1.5
  circle A15 centre (21.5, 8.5) radius 1.5
  circle A16 centre (-21.5, -8.5) radius 1.5
  circle A17 centre (-21.5, 8.5) radius 1.5
  constraint coincident L18.end L19.start
  constraint coincident L17.end L18.start
  constraint coincident L21.end L22.start
  constraint coincident L22.end L23.start
  constraint equal A14 A15
  constraint equal A15 A17
  constraint equal A16 A17
extrude "Extrude23" cut sketch "Sketch20" against normal blind 5 contours L18 L19 A14 | L18 L19 A14 | L17 L18 A15 | L17 L18 A15 | L22 L23 A17 | L22 L23 A17 | L21 L22 A16 | L21 L22 A16

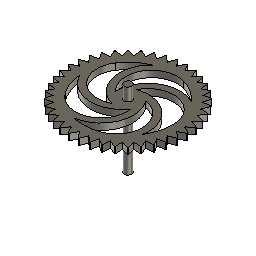
design "in gear"
part number: 2026-03-27-23-33-12-431
Autodesk Fusion 360 part; units mm, degrees
sketch "Sketch1" plane through (0, 0, 0) normal (0, 0, 1) x (1, 0, 0)
  circle A0 centre (0, 0) radius 3
  dimension "d1" = 6
  constraint coincident A0.centre origin
  measures "d1" diameter of A0
extrude "Extrude1" add sketch "Sketch1" along normal blind 49.5
sketch "Sketch2" plane through (0, 0, 49.5) normal (0, 0, 1) x (-1, 0, 0)
  circle A0 centre (0, 0) radius 3
  circle A1 centre (0, 0) radius 41
  dimension "d4" = 82
  constraint concentric A0 A1
  measures "d4" diameter of A1
extrude "Extrude2" add sketch "Sketch2" against normal blind 5
sketch "Sketch3" plane through (0, 0, 49.5) normal (0, 0, 1) x (-1, 0, 0)
  circle A0 centre (0, 0) radius 41
  line L0 (-3.4641, -40.8534) -> (0, -46.8534)
  line L1 (0, -46.8534) -> (3.4641, -40.8534)
  line L2 (3.4641, -40.8534) -> (-3.4641, -40.8534)
  point P0 (0, -42.8534)
  dimension "d7" = 2
  constraint horizontal L2
  constraint coincident A0 L1.end
  constraint coincident A0 L0.start
  measures "d7" distance of P0 L2
extrude "Extrude3" add sketch "Sketch3" against normal up to surface (5 mm away) contours A0 L0 L1
fillet "Fillet1" radius 0.5 1 edges at (0, 46.8534, 47)
pattern_circular "C-Pattern1" count 40 over 360 about axis through (0, 0, 1.75) along (0, 0, 1) of "Extrude3", "Fillet1"
sketch "Sketch4" plane through (0, 0, 49.5) normal (0, 0, 1) x (-1, 0, 0)
  arc A0 (-7.6398, -45.468) -> (-6.7845, -45.6035) centre (-7.1731, -45.2889) ccw
  line L0 (-6.7845, -45.6035) -> (-3.2451, -41.2327)
  line L1 (-3.2451, -41.2327) -> (-0.433, -46.1034)
  arc A1 (-0.433, -46.1034) -> (0.433, -46.1034) centre (0, -45.8534) ccw
  line L2 (0.433, -46.1034) -> (3.2451, -41.2327)
  line L3 (3.2451, -41.2327) -> (6.7845, -45.6035)
  arc A2 (6.7845, -45.6035) -> (7.6398, -45.468) centre (7.1731, -45.2889) ccw
  line L4 (7.6398, -45.468) -> (9.6554, -40.2175)
  line L5 (9.6554, -40.2175) -> (13.8349, -43.9807)
  arc A3 (13.8349, -43.9807) -> (14.6586, -43.7131) centre (14.1695, -43.6092) ccw
  line L6 (14.6586, -43.7131) -> (15.8279, -38.2119)
  line L7 (15.8279, -38.2119) -> (20.5447, -41.275)
  arc A4 (20.5447, -41.275) -> (21.3163, -40.8818) centre (20.817, -40.8557) ccw
  line L8 (21.3163, -40.8818) -> (21.6107, -35.2654)
  line L9 (21.6107, -35.2654) -> (26.7486, -37.5529)
  arc A5 (26.7486, -37.5529) -> (27.4492, -37.0439) centre (26.952, -37.0962) ccw
  line L10 (27.4492, -37.0439) -> (26.8613, -31.4506)
  line L11 (26.8613, -31.4506) -> (32.2938, -32.9062)
  arc A6 (32.2938, -32.9062) -> (32.9062, -32.2938) centre (32.4232, -32.4232) ccw
  line L12 (32.9062, -32.2938) -> (31.4506, -26.8613)
  line L13 (31.4506, -26.8613) -> (37.0439, -27.4492)
  arc A7 (37.0439, -27.4492) -> (37.5529, -26.7486) centre (37.0962, -26.952) ccw
  line L14 (37.5529, -26.7486) -> (35.2654, -21.6107)
  line L15 (35.2654, -21.6107) -> (40.8818, -21.3163)
  arc A8 (40.8818, -21.3163) -> (41.275, -20.5447) centre (40.8557, -20.817) ccw
  line L16 (41.275, -20.5447) -> (38.2119, -15.8279)
  line L17 (38.2119, -15.8279) -> (43.7131, -14.6586)
  arc A9 (43.7131, -14.6586) -> (43.9807, -13.8349) centre (43.6092, -14.1695) ccw
  line L18 (43.9807, -13.8349) -> (40.2175, -9.6554)
  line L19 (40.2175, -9.6554) -> (45.468, -7.6398)
  arc A10 (45.468, -7.6398) -> (45.6035, -6.7845) centre (45.2889, -7.1731) ccw
  line L20 (45.6035, -6.7845) -> (41.2327, -3.2451)
  line L21 (41.2327, -3.2451) -> (46.1034, -0.433)
  arc A11 (46.1034, -0.433) -> (46.1034, 0.433) centre (45.8534, 0) ccw
  line L22 (46.1034, 0.433) -> (41.2327, 3.2451)
  line L23 (41.2327, 3.2451) -> (45.6035, 6.7845)
  arc A12 (45.6035, 6.7845) -> (45.468, 7.6398) centre (45.2889, 7.1731) ccw
  line L24 (45.468, 7.6398) -> (40.2175, 9.6554)
  line L25 (40.2175, 9.6554) -> (43.9807, 13.8349)
  arc A13 (43.9807, 13.8349) -> (43.7131, 14.6586) centre (43.6092, 14.1695) ccw
  line L26 (43.7131, 14.6586) -> (38.2119, 15.8279)
  line L27 (38.2119, 15.8279) -> (41.275, 20.5447)
  arc A14 (41.275, 20.5447) -> (40.8818, 21.3163) centre (40.8557, 20.817) ccw
  line L28 (40.8818, 21.3163) -> (35.2654, 21.6107)
  line L29 (35.2654, 21.6107) -> (37.5529, 26.7486)
  arc A15 (37.5529, 26.7486) -> (37.0439, 27.4492) centre (37.0962, 26.952) ccw
  line L30 (37.0439, 27.4492) -> (31.4506, 26.8613)
  line L31 (31.4506, 26.8613) -> (32.9062, 32.2938)
  arc A16 (32.9062, 32.2938) -> (32.2938, 32.9062) centre (32.4232, 32.4232) ccw
  line L32 (32.2938, 32.9062) -> (26.8613, 31.4506)
  line L33 (26.8613, 31.4506) -> (27.4492, 37.0439)
  arc A17 (27.4492, 37.0439) -> (26.7486, 37.5529) centre (26.952, 37.0962) ccw
  line L34 (26.7486, 37.5529) -> (21.6107, 35.2654)
  line L35 (21.6107, 35.2654) -> (21.3163, 40.8818)
  arc A18 (21.3163, 40.8818) -> (20.5447, 41.275) centre (20.817, 40.8557) ccw
  line L36 (20.5447, 41.275) -> (15.8279, 38.2119)
  line L37 (15.8279, 38.2119) -> (14.6586, 43.7131)
  arc A19 (14.6586, 43.7131) -> (13.8349, 43.9807) centre (14.1695, 43.6092) ccw
  line L38 (13.8349, 43.9807) -> (9.6554, 40.2175)
  line L39 (9.6554, 40.2175) -> (7.6398, 45.468)
  arc A20 (7.6398, 45.468) -> (6.7845, 45.6035) centre (7.1731, 45.2889) ccw
  line L40 (6.7845, 45.6035) -> (3.2451, 41.2327)
  line L41 (3.2451, 41.2327) -> (0.433, 46.1034)
  arc A21 (0.433, 46.1034) -> (-0.433, 46.1034) centre (0, 45.8534) ccw
  line L42 (-0.433, 46.1034) -> (-3.2451, 41.2327)
  line L43 (-3.2451, 41.2327) -> (-6.7845, 45.6035)
  arc A22 (-6.7845, 45.6035) -> (-7.6398, 45.468) centre (-7.1731, 45.2889) ccw
  line L44 (-7.6398, 45.468) -> (-9.6554, 40.2175)
  line L45 (-9.6554, 40.2175) -> (-13.8349, 43.9807)
  arc A23 (-13.8349, 43.9807) -> (-14.6586, 43.7131) centre (-14.1695, 43.6092) ccw
  line L46 (-14.6586, 43.7131) -> (-15.8279, 38.2119)
  line L47 (-15.8279, 38.2119) -> (-20.5447, 41.275)
  arc A24 (-20.5447, 41.275) -> (-21.3163, 40.8818) centre (-20.817, 40.8557) ccw
  line L48 (-21.3163, 40.8818) -> (-21.6107, 35.2654)
  line L49 (-21.6107, 35.2654) -> (-26.7486, 37.5529)
  arc A25 (-26.7486, 37.5529) -> (-27.4492, 37.0439) centre (-26.952, 37.0962) ccw
  line L50 (-27.4492, 37.0439) -> (-26.8613, 31.4506)
  line L51 (-26.8613, 31.4506) -> (-32.2938, 32.9062)
  arc A26 (-32.2938, 32.9062) -> (-32.9062, 32.2938) centre (-32.4232, 32.4232) ccw
  line L52 (-32.9062, 32.2938) -> (-31.4506, 26.8613)
  line L53 (-31.4506, 26.8613) -> (-37.0439, 27.4492)
  arc A27 (-37.0439, 27.4492) -> (-37.5529, 26.7486) centre (-37.0962, 26.952) ccw
  line L54 (-37.5529, 26.7486) -> (-35.2654, 21.6107)
  line L55 (-35.2654, 21.6107) -> (-40.8818, 21.3163)
  arc A28 (-40.8818, 21.3163) -> (-41.275, 20.5447) centre (-40.8557, 20.817) ccw
  line L56 (-41.275, 20.5447) -> (-38.2119, 15.8279)
  line L57 (-38.2119, 15.8279) -> (-43.7131, 14.6586)
  arc A29 (-43.7131, 14.6586) -> (-43.9807, 13.8349) centre (-43.6092, 14.1695) ccw
  line L58 (-43.9807, 13.8349) -> (-40.2175, 9.6554)
  line L59 (-40.2175, 9.6554) -> (-45.468, 7.6398)
  arc A30 (-45.468, 7.6398) -> (-45.6035, 6.7845) centre (-45.2889, 7.1731) ccw
  line L60 (-45.6035, 6.7845) -> (-41.2327, 3.2451)
  line L61 (-41.2327, 3.2451) -> (-46.1034, 0.433)
  arc A31 (-46.1034, 0.433) -> (-46.1034, -0.433) centre (-45.8534, 0) ccw
  line L62 (-46.1034, -0.433) -> (-41.2327, -3.2451)
  line L63 (-41.2327, -3.2451) -> (-45.6035, -6.7845)
  arc A32 (-45.6035, -6.7845) -> (-45.468, -7.6398) centre (-45.2889, -7.1731) ccw
  line L64 (-45.468, -7.6398) -> (-40.2175, -9.6554)
  line L65 (-40.2175, -9.6554) -> (-43.9807, -13.8349)
  arc A33 (-43.9807, -13.8349) -> (-43.7131, -14.6586) centre (-43.6092, -14.1695) ccw
  line L66 (-43.7131, -14.6586) -> (-38.2119, -15.8279)
  line L67 (-38.2119, -15.8279) -> (-41.275, -20.5447)
  arc A34 (-41.275, -20.5447) -> (-40.8818, -21.3163) centre (-40.8557, -20.817) ccw
  line L68 (-40.8818, -21.3163) -> (-35.2654, -21.6107)
  line L69 (-35.2654, -21.6107) -> (-37.5529, -26.7486)
  arc A35 (-37.5529, -26.7486) -> (-37.0439, -27.4492) centre (-37.0962, -26.952) ccw
  line L70 (-37.0439, -27.4492) -> (-31.4506, -26.8613)
  line L71 (-31.4506, -26.8613) -> (-32.9062, -32.2938)
  arc A36 (-32.9062, -32.2938) -> (-32.2938, -32.9062) centre (-32.4232, -32.4232) ccw
  line L72 (-32.2938, -32.9062) -> (-26.8613, -31.4506)
  line L73 (-26.8613, -31.4506) -> (-27.4492, -37.0439)
  arc A37 (-27.4492, -37.0439) -> (-26.7486, -37.5529) centre (-26.952, -37.0962) ccw
  line L74 (-26.7486, -37.5529) -> (-21.6107, -35.2654)
  line L75 (-21.6107, -35.2654) -> (-21.3163, -40.8818)
  arc A38 (-21.3163, -40.8818) -> (-20.5447, -41.275) centre (-20.817, -40.8557) ccw
  line L76 (-20.5447, -41.275) -> (-15.8279, -38.2119)
  line L77 (-15.8279, -38.2119) -> (-14.6586, -43.7131)
  arc A39 (-14.6586, -43.7131) -> (-13.8349, -43.9807) centre (-14.1695, -43.6092) ccw
  line L78 (-13.8349, -43.9807) -> (-9.6554, -40.2175)
  line L79 (-9.6554, -40.2175) -> (-7.6398, -45.468)
  circle A40 centre (0, 0) radius 35
  circle A41 centre (0, 0) radius 5
  arc A42 (-34.9762, -1.2899) -> (4.9966, 0.1843) centre (-14.9898, -0.5528) ccw
  arc A43 (-26.6834, -22.6495) -> (10.0084, -0.2575) centre (-14.9898, -0.5528) ccw
  arc A44 (-9.5814, -33.663) -> (1.3688, 4.809) centre (-4.1063, -14.427) ccw
  arc A45 (13.2953, -32.3765) -> (3.3377, 9.439) centre (-4.1063, -14.427) ccw
  arc A46 (29.0546, -19.5149) -> (-4.1507, 2.7878) centre (12.452, -8.3635) ccw
  arc A47 (34.9003, 2.6397) -> (-7.9456, 6.0912) centre (12.452, -8.3635) ccw
  arc A48 (27.5381, 21.6021) -> (-3.934, -3.086) centre (11.8021, 9.258) ccw
  arc A49 (8.2743, 34.0079) -> (-8.2484, -5.6745) centre (11.8021, 9.258) ccw
  arc A50 (-12.0351, 32.8657) -> (1.7193, -4.6951) centre (-5.1579, 14.0853) ccw
  arc A51 (-29.7865, 18.3783) -> (2.8478, -9.5982) centre (-5.1579, 14.0853) ccw
  dimension "d14" = 70
  dimension "d15" = 10
  constraint coincident A40.centre A41.centre
  constraint tangent A40 A42
  constraint tangent A41 A42
  constraint coincident A41 A42.end
  constraint coincident A40 A42.start
  constraint coincident A40 A47.start
  constraint coincident A46 A45.end
  constraint concentric A42 A43
  constraint coincident A44 A43.end
  constraint coincident A42 A51.end
  constraint coincident A50 A49.end
  constraint coincident A48 A47.end
  constraint coincident A40 A49.start
  constraint coincident A40 A51.start
  constraint coincident A40 A43.start
  constraint coincident A40 A45.start
  measures "d14" diameter of A40
  measures "d15" diameter of A41